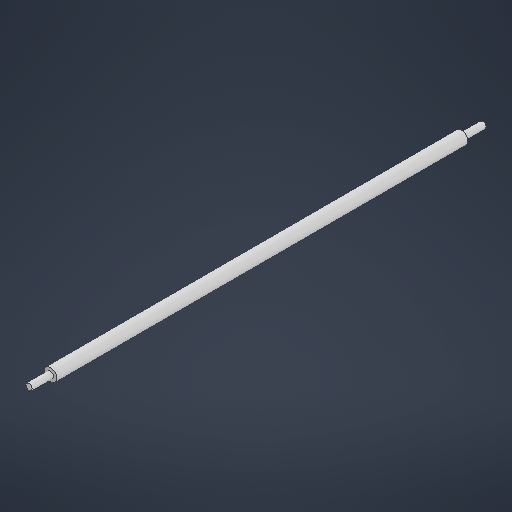
# Autodesk Inventor part: Axe_Roues_arr_Grobot
Saved by Autodesk Inventor 2026 (Build 300175050, 175E)
## iProperties
Created: 2025-05-12
Part Number: Axe_Roues_arr_Grobot
Material: Générique
Document SubType Name: Modeling
Designer: Diogo
Density: 1 g/cm^3
Appearance: Par défaut
Author: Diogo
Autodesk Inventor part; units mm, degrees
ref_plane "YZ Plane" through (0, 0, 0) normal (1, 0, 0) x (0, 1, 0)
ref_plane "XZ Plane" through (0, 0, 0) normal (0, 1, 0) x (-1, 0, 0)
ref_plane "XY Plane" through (0, 0, 0) normal (0, 0, 1) x (1, 0, 0)
sketch "Esquisse1" plane through (0, 0, 0) normal (1, 0, 0) x (0, 1, 0)
  line L0 (5, 0) -> (5, -162.75)
  line L1 (5, -162.75) -> (2.5, -162.75)
  line L2 (0, -162.75) -> (0, 0)
  line L3 (2.5, -162.75) -> (2.5, -179.75)
  line L4 (2.5, -179.75) -> (0, -179.75)
  line L5 (0, -179.75) -> (0, -162.75)
  line L6 (51.4193, 0) -> (-65.7696, 0) construction
  line L7 (5, 0) -> (5, 162.75)
  line L8 (5, 162.75) -> (2.5, 162.75)
  line L9 (0, 162.75) -> (0, 0)
  line L10 (2.5, 162.75) -> (2.5, 179.75)
  line L11 (2.5, 179.75) -> (0, 179.75)
  line L12 (0, 179.75) -> (0, 162.75)
  line L13 (0, -251.65) -> (0, 251.65) projected
  dimension "d3" = 162.75
  dimension "d4" = 17
  dimension "d5" = 2.5
  dimension "d6" = 162.75
  dimension "d8" = 5
  dimension "d9" = 2.5
  constraints: 26 end point, 5 symmetric about line, 2 parallel, 1 horizontal
  measures "d3" distance of L0.start L0.end
  measures "d4" distance of L1.end L3.end
  measures "d5" distance of L3.end L4.end
  measures "d6" distance of L0.start L7.end
  measures "d8" distance between parallel lines of L13 L0
  measures "d9" distance between parallel lines of L13 L3
revolve "Révolution1" add sketch "Esquisse1" angle 360 about axis through (0, 0, -10) along (0, 0, 1)
